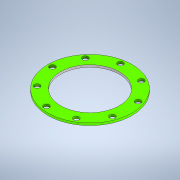
# Autodesk Inventor part: 3_flansa_fixare_bete_verticale_sus_4mm
Saved by Autodesk Inventor 2022.6 (Build 266554000, 554)
## iProperties
Created: 2025-09-01
Part Number: 3_flansa_fixare_bete_verticale_sus_4mm
Material: Generic
Document SubType Name: Modeling
Designer: Dragos Macovei
Density: 1 g/cm^3
Appearance: Default
Author: Dragos Macovei
Autodesk Inventor part; units mm, degrees
ref_plane "YZ Plane" through (0, 0, 0) normal (1, 0, 0) x (0, 1, 0)
ref_plane "XZ Plane" through (0, 0, 0) normal (0, 1, 0) x (-1, 0, 0)
ref_plane "XY Plane" through (0, 0, 0) normal (0, 0, 1) x (1, 0, 0)
sketch "Sketch1" plane through (0, 0, 0) normal (0, 1, 0) x (-1, 0, 0)
  circle A0 centre (0, 0) radius 75
  dimension "d0" = 150
  constraints: 1 centre point, 1 coincident
  measures "d0" diameter of A0
extrude "Extrusion1" add sketch "Sketch1" along normal blind 4
sketch "Sketch2" plane through (0, 4, 0) normal (0, 1, 0) x (1, 0, 0)
  circle A0 centre (0, 0) radius 75 projected
  circle A1 centre (-67, 0) radius 5
  circle A2 centre (-51.325, -43.0668) radius 5
  circle A3 centre (-11.6344, -65.9821) radius 5
  circle A4 centre (33.5, -58.0237) radius 5
  circle A5 centre (62.9594, -22.9153) radius 5
  circle A6 centre (62.9594, 22.9153) radius 5
  circle A7 centre (33.5, 58.0237) radius 5
  circle A8 centre (-11.6344, 65.9821) radius 5
  circle A9 centre (-51.325, 43.0668) radius 5
  dimension "d3" = 10
  dimension "d4" = 3
  dimension "d7" = 360
  constraints: 9 centre point, 19 other
  measures "d3" diameter of A1
extrude "Extrusion2" cut sketch "Sketch2" against normal through all contours A1 | A2 | A3 | A4 | A5 | A6 | A7 | A8 | A9
sketch "Sketch4" plane through (0, 4, 0) normal (0, 1, 0) x (1, 0, 0)
  circle A0 centre (0, 0) radius 52.5
  dimension "d12" = 105
  constraints: 1 centre point
  measures "d12" diameter of A0
extrude "Extrusion3" cut sketch "Sketch4" against normal through all
body "Solid1"
